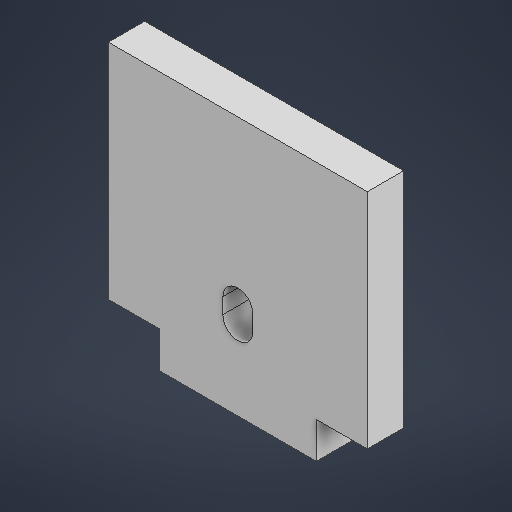
# Autodesk Inventor part: test2
Saved by Autodesk Inventor 2027.1 (Build 311270010, 270A)
## iProperties
Created: 2026-11-15
Part Number: test2
Material: Generic
Document SubType Name: Modeling
Designer: SDS Scholar
Density: 1 g/cm^3
Appearance: Default
Author: SDS Scholar
Autodesk Inventor part; units mm, degrees
ref_plane "YZ Plane" through (0, 0, 0) normal (1, 0, 0) x (0, 1, 0)
ref_plane "XZ Plane" through (0, 0, 0) normal (0, 1, 0) x (-1, 0, 0)
ref_plane "XY Plane" through (0, 0, 0) normal (0, 0, 1) x (1, 0, 0)
sketch "Sketch1" plane through (0, 0, 0) normal (0, 0, 1) x (1, 0, 0)
  line L0 (-25, 25) -> (25, 25)
  line L1 (25, 25) -> (25, -25)
  line L2 (25, -25) -> (-25, -25)
  line L3 (-25, -25) -> (-25, 25)
  line L4 (-25, 25) -> (25, -25) construction
  line L5 (25, 25) -> (-25, -25) construction
  line L6 (-25, -18) -> (25, -18)
  line L7 (-15.15, -18) -> (15.15, -18)
  line L8 (15.15, -18) -> (15.15, -25)
  line L9 (15.15, -25) -> (-15.15, -25)
  line L10 (-15.15, -25) -> (-15.15, -18)
  line L11 (0, -9.5) -> (0, -6.5) construction
  line L12 (2.9, -9.5) -> (2.9, -6.5)
  line L13 (-2.9, -6.5) -> (-2.9, -9.5)
  arc A0 (-2.9, -9.5) -> (2.9, -9.5) centre (0, -9.5) ccw
  arc A1 (2.9, -6.5) -> (-2.9, -6.5) centre (0, -6.5) ccw
  point P0 (0, 0)
  point P1 (0, -18)
  point P2 (0, -18)
  point P3 (0, -8)
  dimension "d0" = 50
  dimension "d1" = 50
  dimension "d2" = 7
  dimension "d3" = 30.3
  dimension "d4" = 5.8
  dimension "d5" = 8.5
  dimension "d6" = 3
  constraints: 30 end point, 5 midpoint, 5 parallel, 4 perpendicular, 4 point on circle, 4 point on line, 4 tangent, 2 centre point, 2 horizontal, 1 coincident, 1 vertical alignment
  measures "d0" distance of L1.end L2.end
  measures "d1" distance of L0.end L1.end
  measures "d2" distance between parallel lines of L2 L6
  measures "d3" distance between parallel lines of L8 L10
  measures "d4" diameter of A1
  measures "d5" distance from line of L11.start L7
  measures "d6" distance of L11.start L11.end
extrude "Extrusion1" add sketch "Sketch1" along normal blind 7 contours L0 L1 L6 L3 | L6 L8 L2 L10
body "Solid1"
